Autodesk Inventor part; units mm, degrees
(part 2 of 2)
equation "\"d3\" = da_b"
equation "\"d4\" = da_ve"
equation "\"d7\" = fd_rr"
equation "\"d8\" = fd_x"
equation "\"d9\" = fd_y"
equation "\"d57\" = 0.5 * fd_dva + 0.3 * da_he"
equation "\"d58\" = 0.5 * fd_dva - 1.12 * da_he"
equation "\"da_teethtype\" = 0"
equation "\"da_b\" = 10"
equation "\"da_de\" = 99"
equation "\"da_dae\" = 99.33926"
equation "\"da_dfe\" = 97.87656"
equation "\"da_le\" = 50.76231"
equation "\"da_omega\" = 90deg"
equation "\"da_beta\" = 0"
equation "\"da_delta\" = 77.195734deg"
equation "\"da_alpha\" = 20deg"
equation "\"da_he\" = 3.3"
equation "\"da_ve\" = 10.50362"
equation "\"da_zv\" = 297.805574"
equation "\"fd_loft\" = da_b + 0.05 * da_he"
equation "\"fd_x\" = fd_x1 + fd_x2"
equation "\"fd_y\" = fd_y1 - fd_y2"
equation "\"fd_dd\" = fd_dva - 0.8 * da_he"
equation "\"da_dvw\" = 445.23919"
equation "\"d11\" = fd_loft"
equation "\"da_dm\" = 89.24867"
equation "\"da_x\" = -0.489724"
equation "\"da_m\" = 1.5"
equation "\"d50\" = da_omega"
equation "\"fd_rr\" = 74.754599"
equation "\"fd_dva\" = 448.239188"
equation "\"fd_x1\" = 1.187264"
equation "\"fd_x2\" = 70.720017"
equation "\"fd_y1\" = 222.616428"
equation "\"fd_y2\" = 24.226624"
body "Solid1"
body "Srf1"
